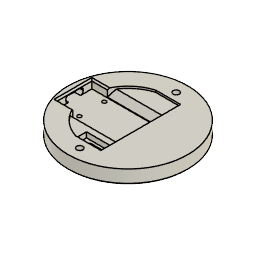
DialScroll (Autodesk Fusion 360 design; units mm, degrees)
Autodesk Fusion 360 part; units mm, degrees
sketch "Sketch1" plane through (0, 0, 0) normal (0, 0, 1) x (1, 0, 0)
  circle A0 centre (0, 0) radius 22.5
  circle A1 centre (0, 0) radius 29
  dimension "d1" = 45
  dimension "d2" = 58
  constraint coincident A0.centre A1.centre
  measures "d1" diameter of A0
  measures "d2" diameter of A1
extrude "Extrude1" add sketch "Sketch1" along normal blind 7 makes body 1
chamfer "Chamfer1" distance 1 angle 45 4 edges at (-27.0375, -10.4868, 7) (-27.0375, -10.4868, 0) (-20.9774, 8.1363, 7) (-20.9774, 8.1363, 0) on bodies 1
ref_plane "WorkPlane1" through (0, 0, -2) normal (0, 0, -1) x (-1, 0, 0)
sketch "Sketch2" plane through (0, 0, -2) normal (0, 0, -1) x (-1, 0, 0)
  line L0 (-21.5, 15) -> (21.5, 15)
  line L1 (21.5, 15) -> (21.5, -15)
  line L2 (21.5, -15) -> (-21.5, -15)
  line L3 (-21.5, -15) -> (-21.5, 15)
  line L4 (-21.5, 15) -> (21.5, -15) construction
  line L5 (21.5, 15) -> (-21.5, -15) construction
  dimension "d7" = 43
  dimension "d8" = 30
  constraint horizontal L0
  constraint perpendicular L0 L1
  constraint parallel L0 L2
  constraint parallel L1 L3
  constraint coincident L4 origin
  constraint coincident L5 origin
  measures "d7" distance of L1.end L2.end
  measures "d8" distance of L0.end L1.end
extrude "Extrude2" add sketch "Sketch2" along normal blind 10 separate body makes body 2
ref_plane "WorkPlane2" through (0, 0, -12.3) normal (0, 0, -1) x (-1, 0, 0)
sketch "Sketch3" plane through (0, 0, -12.3) normal (0, 0, -1) x (-1, 0, 0)
  line L0 (-16.75, 9) -> (16.75, 9)
  line L1 (16.75, 9) -> (16.75, -9)
  line L2 (16.75, -9) -> (-16.75, -9)
  line L3 (-16.75, -9) -> (-16.75, 9)
  line L4 (-16.75, 9) -> (16.75, -9) construction
  line L5 (16.75, 9) -> (-16.75, -9) construction
  dimension "d12" = 33.5
  dimension "d13" = 18
  constraint horizontal L0
  constraint perpendicular L0 L1
  constraint parallel L0 L2
  constraint parallel L1 L3
  constraint coincident L4 origin
  constraint coincident L5 origin
  measures "d12" distance of L1.end L2.end
  measures "d13" distance of L0.end L1.end
extrude "Extrude3" add sketch "Sketch3" along normal blind 4.3 separate body makes body 3
ref_plane "WorkPlane4" through (0, 0, 7.6) normal (0, 0, 1) x (1, 0, 0)
sketch "Sketch6" plane through (0, 0, 7.6) normal (0, 0, 1) x (1, 0, 0)
  circle A0 centre (0, 0) radius 29
  circle A1 centre (0, 0) radius 31
  dimension "d23" = 58
  dimension "d24" = 2
  constraint coincident A0.centre A1.centre
  measures "d23" diameter of A0
extrude "Extrude4" add sketch "Sketch6" along normal blind 2 separate body contours A0 | A1 makes body 4
sketch "Sketch7" plane through (0, 0, 7.6) normal (0, 0, -1) x (1, 0, 0)
  circle A0 centre (0, 0) radius 31
  circle A1 centre (0, 0) radius 29.8
  dimension "d27" = -1.2
extrude "Extrude5" add sketch "Sketch7" along normal blind 19.6 bodies 4
sketch "Sketch8" plane through (0, 0, 7.6) normal (0, 0, -1) x (1, 0, 0)
  circle A0 centre (0, 0) radius 29.8
  circle A1 centre (0, 0) radius 26.8
  dimension "d30" = -3
extrude "Extrude6" add sketch "Sketch8" along normal blind 0.6 bodies 4
sketch "Sketch9" plane through (0, 0, 7) normal (0, 0, -1) x (1, 0, 0)
  circle A0 centre (0, 0) radius 26.8
  circle A1 centre (0, 0) radius 29.8
  circle A2 centre (0, 0) radius 29
  dimension "d33" = -0.8
extrude "Extrude7" add sketch "Sketch9" along normal blind 5.8 contours A1 bodies 4
fillet "Fillet1" radius 0.5 1 edges at (-27.0375, 10.4868, 7) on bodies 4
fillet "Fillet2" radius 4 1 edges at (-28.9021, -11.2101, 9.6) on bodies 4
sketch "Sketch10" plane through (0, 0, 7.6) normal (0, 0, -1) x (1, 0, 0)
  circle A0 centre (0, 0) radius 26.8
  circle A1 centre (0, 0) radius 2.05
  circle A2 centre (0, 0) radius 4.05
  dimension "d40" = 4.1
  dimension "d41" = 2
  constraint coincident A0.centre A1.centre
  measures "d40" diameter of A1
extrude "Extrude8" add sketch "Sketch10" along normal blind 2 contours A2 bodies 4
chamfer "Chamfer2" distance 0.8 angle 45 1 edges at (-1.9113, -0.7413, 5.6) on bodies 4
chamfer "Chamfer3" distance 2 angle 45 1 edges at (-3.7759, -1.4645, 7.6) on bodies 4
ref_plane "WorkPlane5" through (0, 0, 4.6) normal (0, 0, -1) x (-1, 0, 0)
sketch "Sketch11" plane through (0, 0, 4.6) normal (0, 0, -1) x (-1, 0, 0)
  line L0 (11.5, -11.5) -> (-11.5, -11.5)
  line L1 (-11.5, -11.5) -> (-11.5, 11.5)
  line L2 (-11.5, 11.5) -> (11.5, 11.5)
  line L3 (11.5, 11.5) -> (11.5, -11.5)
  line L4 (11.5, -11.5) -> (-11.5, 11.5) construction
  line L5 (-11.5, -11.5) -> (11.5, 11.5) construction
  circle A0 centre (-8.9, 8.9) radius 1.2
  circle A1 centre (8.9, 8.9) radius 1.2
  circle A2 centre (-8.9, -8.9) radius 1.2
  circle A3 centre (8.9, -8.9) radius 1.2
  dimension "d49" = 23
  dimension "d50" = 23
  dimension "d51" = 2.4
  dimension "d52" = 2.6
  dimension "d53" = 2.4
  dimension "d54" = 2.4
  dimension "d55" = 2.4
  dimension "d56" = 2.6
  dimension "d57" = 2.6
  dimension "d58" = 2.6
  constraint horizontal L0
  constraint perpendicular L0 L1
  constraint parallel L0 L2
  constraint parallel L1 L3
  constraint coincident L4 origin
  constraint coincident L5 origin
  constraint coincident L4 A0.centre
  constraint coincident L5 A1.centre
  constraint coincident L5 A2.centre
  constraint coincident L4 A3.centre
  measures "d49" distance of L1.end L2.end
  measures "d50" distance of L0.end L1.end
  measures "d51" diameter of A0
  measures "d52" distance of L1 A0.centre
  measures "d53" diameter of A1
  measures "d54" diameter of A2
  measures "d55" diameter of A3
  measures "d56" distance of L3 A1.centre
  measures "d57" distance of L3 A3.centre
  measures "d58" distance of L1 A2.centre
extrude "Extrude9" add sketch "Sketch11" along normal blind 1.6 separate body makes body 5
fillet "Fillet4" radius 1.8 4 edges at (11.5, 11.5, 3.8) (-11.5, 11.5, 3.8) (-11.5, -11.5, 3.8) (11.5, -11.5, 3.8) on bodies 5
extrude "Extrude10" add 1 faces at (-0.5164, -0.0252, 7.6) along direction (0, 0, -1) blind 2 separate body on bodies 4 makes body 6
ref_plane "WorkPlane6" through (0, 0, -0.3) normal (0, 0, -1) x (-1, 0, 0)
sketch "Sketch13" plane through (0, 0, -0.3) normal (0, 0, -1) x (-1, 0, 0)
  circle A0 centre (0, 0) radius 29
  dimension "d66" = 58
  constraint coincident A0.centre origin
  measures "d66" diameter of A0
extrude "Extrude11" add sketch "Sketch13" along normal blind 2 separate body makes body 7
sketch "Sketch14" plane through (0, 0, -0.3) normal (0, 0, 1) x (-1, 0, 0)
  circle A0 centre (0, 0) radius 29
  circle A1 centre (0, 0) radius 22.5
  circle A2 centre (0, 0) radius 20.5
  dimension "d69" = 45
  dimension "d70" = -2
  constraint coincident A0.centre A1.centre
  measures "d69" diameter of A1
extrude "Extrude12" add sketch "Sketch14" along normal blind 7 contours A1 bodies 1 7
fillet "Fillet6" radius 0.5 1 edges at (20.9774, 8.1363, 6.7) on bodies 1
fillet "Fillet8" radius 0.5 1 edges at (27.0375, -10.4868, -0.3) on bodies 1 7
extrude "Extrude15" add 1 faces at (8.3085, 6.854, -2.3) along direction (0, 0, -1) blind 9.7 on bodies 1 bodies 1
combine "Combine2" operation cut target body 1 tool bodies 2 keep tools
extrude "Extrude20" cut 1 faces at (-8.0163, 5.1011, -0.3) along direction (0, 0, -1) blind 15 on bodies 1 bodies 1
sketch "Sketch25" plane through (0, 0, -0.3) normal (0, 0, 1) x (-1, 0, 0)
  circle A0 centre (0, 0) radius 22.5
  circle A1 centre (0, 0) radius 28.5
  circle A2 centre (0, 0) radius 25.5
  dimension "d117" = 3
extrude "Extrude21" add sketch "Sketch25" along normal blind 0.3 contours A2 bodies 1
extrude "Extrude22" add 1 faces at (23.5705, -2.8493, -12) along direction (0, 0, -1) blind 0.6 on bodies 1 bodies 1
move_body "Move1" bodies 3 to x (1, 0, 0) y (0, 1, 0) z (0, 0, 1) at (0, 0, -0.3)
sketch "Sketch27" plane through (0, 0, 6.7) normal (0, 0, 1) x (-1, 0, 0)
  circle A0 centre (0, 0) radius 20.5
  circle A1 centre (0, 0) radius 22
  circle A2 centre (0, 0) radius 9.5
  dimension "d122" = -11
extrude "Extrude23" add sketch "Sketch27" against normal blind 3.3 contours A0 bodies 1
move_body "Move2" bodies 5 to x (1, 0, 0) y (0, 1, 0) z (0, 0, 1) at (0, 0, -0.9)
sketch "Sketch29" plane through (0, 0, 3.4) normal (0, 0, -1) x (1, 0, 0)
  circle A0 centre (0, 0) radius 9.5
  circle A1 centre (0, 0) radius 20.5
  circle A2 centre (0, 0) radius 11.5
  dimension "d125" = 2
extrude "Extrude24" cut sketch "Sketch29" against normal blind 0.009 contours A2 bodies 1
sketch "Sketch30" plane through (0, 0, 2.1) normal (0, 0, -1) x (1, 0, 0)
  arc A0 (11.5, 9.7) -> (9.7, 11.5) centre (9.7, 9.7) ccw
  line L0 (9.7, 11.5) -> (-9.7, 11.5)
  arc A1 (-9.7, 11.5) -> (-11.5, 9.7) centre (-9.7, 9.7) ccw
  line L1 (-11.5, 9.7) -> (-11.5, -9.7)
  arc A2 (-11.5, -9.7) -> (-9.7, -11.5) centre (-9.7, -9.7) ccw
  line L2 (-9.7, -11.5) -> (9.7, -11.5)
  arc A3 (9.7, -11.5) -> (11.5, -9.7) centre (9.7, -9.7) ccw
  line L3 (11.5, -9.7) -> (11.5, 9.7)
  circle A4 centre (8.9, -8.9) radius 1.2
  circle A5 centre (-8.9, 8.9) radius 1.2
  circle A6 centre (8.9, 8.9) radius 1.2
  circle A7 centre (-8.9, -8.9) radius 1.2
  circle A8 centre (-8.9, 8.9) radius 0.9
  circle A9 centre (8.9, 8.9) radius 0.9
  circle A10 centre (-8.9, -8.9) radius 0.9
  circle A11 centre (8.9, -8.9) radius 0.9
  dimension "d134" = 1.8
  dimension "d135" = 1.8
  dimension "d136" = 1.8
  dimension "d137" = 1.8
  constraint concentric A5 A8
  constraint concentric A6 A9
  constraint concentric A7 A10
  constraint concentric A4 A11
  measures "d134" diameter of A8
  measures "d135" diameter of A9
  measures "d136" diameter of A10
  measures "d137" diameter of A11
extrude "Extrude25" cut sketch "Sketch30" against normal blind 10 contours A8 | A9 | A10 | A11 bodies 1
sketch "Sketch31" plane through (0, 0, -12.6) normal (0, 0, -1) x (1, 0, 0)
  arc A0 (-13.9732, -15) -> (13.9732, -15) centre (0, 0) ccw
  line L0 (-13.9732, -15) -> (-21.5, -15)
  line L1 (-21.5, -15) -> (-21.5, 15)
  line L2 (-21.5, 15) -> (-13.9732, 15)
  arc A1 (13.9732, 15) -> (-13.9732, 15) centre (0, 0) ccw
  line L3 (13.9732, 15) -> (21.5, 15)
  line L4 (21.5, 15) -> (21.5, -15)
  line L5 (21.5, -15) -> (13.9732, -15)
  circle A2 centre (0, 0) radius 29
  circle A3 centre (0, 0) radius 31
  dimension "d140" = 2
extrude "Extrude26" add sketch "Sketch31" along normal blind 7 separate body contours A2 | A3 makes body 8
ref_plane "WorkPlane7" through (0, 0, 7) normal (0, 0, 1) x (1, 0, 0)
sketch "Sketch32" plane through (0, 0, 7) normal (0, 0, 1) x (1, 0, 0)
  circle A0 centre (0, 0) radius 22.5
  circle A1 centre (0, 0) radius 29
  dimension "d144" = 45
  dimension "d145" = 58
  constraint coincident A0.centre A1.centre
  measures "d144" diameter of A0
  measures "d145" diameter of A1
extrude "Extrude27" cut sketch "Sketch32" against normal blind 7 bodies 1
sketch "Sketch33" plane through (0, 0, 0) normal (0, 0, 1) x (-1, 0, 0)
  circle A0 centre (0, 0) radius 25.5
  circle A1 centre (0, 0) radius 22.5
  circle A2 centre (0, 0) radius 22.5
  circle A3 centre (0, 0) radius 29
  dimension "d148" = 45
  dimension "d149" = 58
  constraint coincident A0.centre A1.centre
  measures "d148" diameter of A2
  measures "d149" diameter of A3
extrude "Extrude28" add sketch "Sketch33" along normal blind 7 separate body contours A0 | A3 makes body 9
chamfer "Chamfer4" distance 1 angle 45 4 edges at (27.0375, 10.4868, 7) (20.9774, -8.1363, 7) (20.9774, -8.1363, 0) (27.0375, 10.4868, 0) on bodies 9
sketch "Sketch34" plane through (0, 0, -19.6) normal (0, 0, -1) x (1, 0, 0)
  arc A0 (13.9732, 15) -> (-13.9732, 15) centre (0, 0) ccw
  line L0 (13.9732, 15) -> (21.5, 15)
  line L1 (21.5, 15) -> (21.5, -15)
  line L2 (21.5, -15) -> (13.9732, -15)
  arc A1 (-13.9732, -15) -> (13.9732, -15) centre (0, 0) ccw
  line L3 (-13.9732, -15) -> (-21.5, -15)
  line L4 (-21.5, -15) -> (-21.5, 15)
  line L5 (-21.5, 15) -> (-13.9732, 15)
  circle A2 centre (0, 0) radius 31
  circle A3 centre (0, 0) radius 31
  dimension "d153" = 62
  constraint coincident A0.centre A1.centre
  measures "d153" diameter of A3
extrude "Extrude29" add sketch "Sketch34" against normal blind 3 contours A0 L0 L1 L2 A1 L3 L4 L5 | A2 A3 bodies 8
sketch "Sketch35" plane through (-16.75, 0, 0) normal (-1, 0, 0) x (0, -1, 0)
  line L0 (9, -12.6) -> (-9, -12.6)
  line L1 (-9, -12.6) -> (-9, -16.9)
  line L2 (-9, -16.9) -> (9, -16.9)
  line L3 (9, -16.9) -> (9, -12.6)
  line L4 (4.55, -20.3) -> (-4.55, -20.3)
  line L5 (-4.55, -20.3) -> (-4.55, -13.5)
  line L6 (-4.55, -13.5) -> (4.55, -13.5)
  line L7 (4.55, -13.5) -> (4.55, -20.3)
  line L8 (4.55, -20.3) -> (-4.55, -13.5) construction
  line L9 (-4.55, -20.3) -> (4.55, -13.5) construction
  point P0 (0, -16.9)
  dimension "d156" = 9.1
  dimension "d157" = 6.8
  constraint horizontal L4
  constraint perpendicular L4 L5
  constraint parallel L4 L6
  constraint parallel L5 L7
  constraint coincident L8 P0
  constraint coincident L9 P0
  constraint midpoint L2 P0
  measures "d156" distance of L5.end L6.end
  measures "d157" distance of L4.end L5.end
extrude "Extrude30" add sketch "Sketch35" along normal blind 4 contours L2 L5 L6 L7 bodies 3
move_body "Move3" bodies 3 to x (1, 0, 0) y (0, 1, 0) z (0, 0, 1) at (-11, 0, 0)
extrude "Extrude31" add 1 faces at (-0.6191, -5, -16.6) along direction (0, 0, 1) blind 4 on bodies 8 bodies 8
fillet "Fillet13" radius 1.5 4 edges at (-29.75, 4.55, -13.5) (-29.75, 4.55, -16.9) (-29.75, -4.55, -16.9) (-29.75, -4.55, -13.5) on bodies 3
sketch "Sketch38" plane through (0, 0, -19.6) normal (0, 0, -1) x (1, 0, 0)
  circle A0 centre (0, 0) radius 31
  circle A1 centre (0, -25) radius 1.35
  circle A2 centre (0, 25) radius 1.35
  dimension "d168" = 2.7
  dimension "d169" = 2.7
  dimension "d170" = 25
  dimension "d171" = 25
  measures "d168" diameter of A1
  measures "d169" diameter of A2
  measures "d170" distance of A0.centre A1.centre
  measures "d171" distance of A0.centre A2.centre
extrude "Extrude32" cut sketch "Sketch38" against normal blind 16 contours A1 | A2 bodies 1 8
sketch "Sketch39" plane through (0, 0, -19.6) normal (0, 0, -1) x (1, 0, 0)
  circle A0 centre (0, 25) radius 1.35
  circle A1 centre (0, -25) radius 1.35
  circle A2 centre (0, 0) radius 31
  circle A3 centre (0, 25) radius 1.6
  circle A4 centre (0, -25) radius 1.6
  dimension "d174" = 3.2
  dimension "d175" = 3.2
  constraint concentric A0 A3
  constraint concentric A1 A4
  measures "d174" diameter of A3
  measures "d175" diameter of A4
extrude "Extrude33" cut sketch "Sketch39" against normal blind 8 contours A3 | A4 bodies 8
sketch "Sketch40" plane through (0, 0, -19.6) normal (0, 0, -1) x (1, 0, 0)
  circle A0 centre (0, 25) radius 1.6
  circle A1 centre (0, -25) radius 1.6
  circle A2 centre (0, 0) radius 31
  circle A3 centre (0, 25) radius 3.5
  circle A4 centre (0, -25) radius 3.5
  dimension "d178" = 7
  dimension "d179" = 7
  constraint concentric A0 A3
  constraint concentric A1 A4
  measures "d178" diameter of A3
  measures "d179" diameter of A4
extrude "Extrude34" cut sketch "Sketch40" against normal blind 4 contours A3 | A4 bodies 8
combine "Combine7" operation cut target body 8 tool bodies 3 keep tools
chamfer "Chamfer7" distance 0.5 angle 45 2 edges at (-3.2631, 23.7343, -19.6) (-3.2631, -26.2657, -19.6) on bodies 8
sketch "Sketch41" plane through (0, 0, -12.6) normal (0, 0, 1) x (-1, 0, 0)
  line L0 (-5.75, -9) -> (-5.75, 9)
  line L1 (-5.75, 9) -> (27.75, 9)
  line L2 (27.75, 9) -> (27.75, -9)
  line L3 (27.75, -9) -> (-5.75, -9)
  circle A0 centre (0, 25) radius 1.6
  circle A1 centre (0, -25) radius 1.6
  circle A2 centre (0, 0) radius 31
  line L4 (0, -15) -> (6.6, -15)
  line L5 (6.6, -15) -> (6.6, -20.6)
  line L6 (6.6, -20.6) -> (0, -20.6)
  line L7 (0, -20.6) -> (0, -15)
  line L8 (0, -15) -> (-6.6, -15)
  line L9 (-6.6, -15) -> (-6.6, -20.6)
  line L10 (-6.6, -20.6) -> (0, -20.6)
  line L11 (0, -20.6) -> (0, -15)
  dimension "d185" = 6.6
  dimension "d186" = 5.6
  dimension "d229" = 5.6
  constraint horizontal L4
  constraint vertical L5
  constraint horizontal L6
  constraint vertical L7
  constraint horizontal L8
  constraint vertical L9
  constraint horizontal L10
  constraint vertical L11
  measures "d185" distance of L4.start L4.end
  measures "d186" distance of L4.start L6.end
  measures "d229" distance of L4.start L6.end
sketch "Sketch45" plane through (0, 0, -12.6) normal (0, 0, 1) x (-1, 0, 0)
  line L0 (-5.75, -9) -> (-5.75, 9)
  line L1 (-5.75, 9) -> (27.75, 9)
  line L2 (27.75, 9) -> (27.75, -9)
  line L3 (27.75, -9) -> (-5.75, -9)
  circle A0 centre (0, 25) radius 1.6
  circle A1 centre (0, -25) radius 1.6
  circle A2 centre (0, 0) radius 31
  line L4 (0, 15) -> (-6.55, 15)
  line L5 (-6.55, 15) -> (-6.55, 20.6)
  line L6 (-6.55, 20.6) -> (0, 20.6)
  line L7 (0, 20.6) -> (0, 15)
  line L8 (0, 15) -> (6.55, 15)
  line L9 (6.55, 15) -> (6.55, 20.6)
  line L10 (6.55, 20.6) -> (0, 20.6)
  line L11 (0, 20.6) -> (0, 15)
  dimension "d198" = 6.55
  dimension "d199" = 5.6
  dimension "d200" = 5.6
  dimension "d230" = 6.55
  constraint horizontal L4
  constraint vertical L5
  constraint horizontal L6
  constraint vertical L7
  constraint horizontal L8
  constraint vertical L9
  constraint horizontal L10
  constraint vertical L11
  measures "d198" distance of L4.start L4.end
  measures "d199" distance of L4.start L6.end
  measures "d200" distance of L4.start L6.end
  measures "d230" distance of L9 L11
extrude "Extrude39" cut sketch "Sketch45" against normal blind 3.7 contours L4 L5 L6 L7 L11 | L7 L8 L9 L10 L11 bodies 8
sketch "Sketch46" plane through (0, 0, -16.3) normal (0, 0, 1) x (-1, 0, 0)
  line L0 (-6.55, 15) -> (6.55, 15)
  line L1 (6.55, 15) -> (6.55, 20.6)
  line L2 (6.55, 20.6) -> (-6.55, 20.6)
  line L3 (-6.55, 20.6) -> (-6.55, 15)
  line L4 (-3.4, 19.2) -> (3.4, 19.2)
  line L5 (3.4, 19.2) -> (3.4, 16.4)
  line L6 (3.4, 16.4) -> (-3.4, 16.4)
  line L7 (-3.4, 16.4) -> (-3.4, 19.2)
  line L8 (-3.4, 19.2) -> (3.4, 16.4) construction
  line L9 (3.4, 19.2) -> (-3.4, 16.4) construction
  point P0 (0, 17.8)
  dimension "d203" = 6.8
  dimension "d204" = 2.8
  dimension "d205" = 2.8
  constraint horizontal L4
  constraint perpendicular L4 L5
  constraint parallel L4 L6
  constraint parallel L5 L7
  constraint coincident L8 P0
  constraint coincident L9 P0
  measures "d203" distance of L5.end L6.end
  measures "d204" distance of L4.end L5.end
  measures "d205" distance of L2 P0
extrude "Extrude40" cut sketch "Sketch46" against normal blind 4 contours L4 L5 L6 L7 bodies 8
sketch "Sketch49" plane through (0, 0, -12.6) normal (0, 0, 1) x (-1, 0, 0)
  line L0 (6.55, 20.6) -> (6.55, 15)
  line L1 (6.55, 15) -> (-6.55, 15)
  line L2 (-6.55, 15) -> (-6.55, 20.6)
  line L3 (-6.55, 20.6) -> (6.55, 20.6)
  line L4 (-5.75, -9) -> (-5.75, 9)
  line L5 (-5.75, 9) -> (27.75, 9)
  line L6 (27.75, 9) -> (27.75, -9)
  line L7 (27.75, -9) -> (-5.75, -9)
  circle A0 centre (0, 25) radius 1.6
  circle A1 centre (0, -25) radius 1.6
  circle A2 centre (0, 0) radius 31
  line L8 (-5.75, 9) -> (6.55, 9)
  line L9 (6.55, 9) -> (6.55, 15)
  line L10 (6.55, 15) -> (-5.75, 15)
  line L11 (-5.75, 15) -> (-5.75, 9)
  arc A3 (19.6536, 9) -> (6.55, 20.6) centre (0, 0) ccw
  constraint horizontal L8
  constraint vertical L9
  constraint horizontal L10
  constraint vertical L11
  constraint coincident L0.end L1.start
  constraint coincident L4.end L5.start
  constraint coincident L5 A3.start
  constraint coincident L0.start L3.end
  constraint coincident A2.centre A3.centre
extrude "Extrude42" cut sketch "Sketch49" against normal blind 1 contours L0 L5 L9 A3 | L1 L5 L8 L9 L10 L11 bodies 8
sketch "Sketch50" plane through (0, 0, -16.9) normal (0, 0, 1) x (-1, 0, 0)
  arc A0 (30.8496, -3.05) -> (30.8496, 3.05) centre (0, 0) ccw
  line L0 (30.8496, 3.05) -> (27.75, 3.05)
  line L1 (27.75, 3.05) -> (27.75, 9)
  line L2 (27.75, 9) -> (-5.75, 9)
  line L3 (-5.75, 9) -> (-5.75, -9)
  line L4 (-5.75, -9) -> (27.75, -9)
  line L5 (27.75, -9) -> (27.75, -3.05)
  line L6 (27.75, -3.05) -> (30.8496, -3.05)
  circle A1 centre (18.75, -6.5) radius 1
  circle A2 centre (18.75, 6.5) radius 1
  line L7 (27.75, 9) -> (27.75, -9)
  dimension "d212" = 2
  dimension "d213" = 2
  dimension "d214" = 2.5
  dimension "d215" = 2.5
  dimension "d216" = 9
  dimension "d217" = 9
  measures "d212" diameter of A1
  measures "d213" diameter of A2
  measures "d214" distance of L4 A1.centre
  measures "d215" distance of L2 A2.centre
  measures "d216" distance of A1.centre L7
  measures "d217" distance of A2.centre L7
extrude "Extrude43" cut sketch "Sketch50" against normal blind 5 contours A1 | A2 bodies 8
sketch "Sketch52" plane through (0, 0, -12.6) normal (0, 0, 1) x (-1, 0, 0)
  circle A0 centre (0, 0) radius 31
  circle A1 centre (0, -25) radius 1.6
  circle A2 centre (0, 25) radius 1.6
  arc A3 (19.6536, 9) -> (6.55, 20.6) centre (0, 0) ccw
  line L0 (19.6536, 9) -> (27.75, 9)
  line L1 (27.75, 9) -> (27.75, -9)
  line L2 (27.75, -9) -> (-5.75, -9)
  line L3 (-5.75, -9) -> (-5.75, 15)
  line L4 (-5.75, 15) -> (-6.55, 15)
  line L5 (-6.55, 15) -> (-6.55, 20.6)
  line L6 (-6.55, 20.6) -> (6.55, 20.6)
  line L7 (-5.75, -9) -> (6.35, -9)
  line L8 (6.35, -9) -> (6.35, -20.7)
  line L9 (6.35, -20.7) -> (-5.75, -20.7)
  line L10 (-5.75, -20.7) -> (-5.75, -9)
  arc A4 (6.35, -20.7) -> (19.693, -9) centre (0, 0) ccw
  dimension "d220" = 12.1
  dimension "d221" = 11.7
  constraint horizontal L7
  constraint vertical L8
  constraint horizontal L9
  constraint vertical L10
  constraint coincident L2.end L3.start
  constraint coincident L2 A4.end
  constraint coincident A0.centre A3.centre
  measures "d220" distance of L2.end L7.end
  measures "d221" distance of L2.end L9.end
extrude "Extrude44" cut sketch "Sketch52" against normal blind 1 contours L2 L8 A4 | L2 L7 L8 L9 L10 bodies 8
chamfer "Chamfer8" distance 3 angle 45 2 edges at (-6.9715, 9, -13.6) (-6.9518, -9, -13.6) on bodies 8
sketch "Sketch53" plane through (0, 0, -19.6) normal (0, 0, -1) x (1, 0, 0)
  circle A0 centre (-18.75, 6.5) radius 1
  circle A1 centre (-18.75, -6.5) radius 1
  line L0 (-3.4, 16.4) -> (-3.4, 19.2)
  line L1 (-3.4, 19.2) -> (3.4, 19.2)
  line L2 (3.4, 19.2) -> (3.4, 16.4)
  line L3 (3.4, 16.4) -> (-3.4, 16.4)
  circle A2 centre (0, -25) radius 4
  circle A3 centre (0, 0) radius 31
  circle A4 centre (0, 25) radius 4
  line L4 (-4.9, 20.7) -> (4.9, 20.7)
  line L5 (4.9, 20.7) -> (4.9, 14.9)
  line L6 (4.9, 14.9) -> (-4.9, 14.9)
  line L7 (-4.9, 14.9) -> (-4.9, 20.7)
  dimension "d225" = -1.5
extrude "Extrude45" cut sketch "Sketch53" against normal blind 1.5 contours L4 L5 L6 L7 bodies 8
chamfer "Chamfer9" distance 1.5 angle 45 4 edges at (0, -20.7, -18.1) (4.9, -17.8, -18.1) (-4.9, -17.8, -18.1) (0, -14.9, -18.1) on bodies 8
sketch "Sketch55" plane through (0, 0, 7.6) normal (0, 0, -1) x (1, 0, 0)
  circle A0 centre (0, 0) radius 26.8
  circle A1 centre (0, 0) radius 6.05
  line L0 (6, -1) -> (-6, -1)
  line L1 (-6, -1) -> (-6, 1)
  line L2 (-6, 1) -> (6, 1)
  line L3 (6, 1) -> (6, -1)
  line L4 (6, -1) -> (-6, 1) construction
  line L5 (-6, -1) -> (6, 1) construction
  line L6 (1, -6) -> (-1, -6)
  line L7 (-1, -6) -> (-1, 6)
  line L8 (-1, 6) -> (1, 6)
  line L9 (1, 6) -> (1, -6)
  line L10 (1, -6) -> (-1, 6) construction
  line L11 (-1, -6) -> (1, 6) construction
  dimension "d231" = 12
  dimension "d232" = 2
  dimension "d233" = 2
  dimension "d234" = 12
  constraint horizontal L0
  constraint perpendicular L0 L1
  constraint parallel L0 L2
  constraint parallel L1 L3
  constraint coincident L4 A0.centre
  constraint coincident L5 A0.centre
  constraint coincident A0.centre A1.centre
  constraint horizontal L6
  constraint perpendicular L6 L7
  constraint parallel L6 L8
  constraint parallel L7 L9
  constraint coincident L10 A0.centre
  constraint coincident L11 A0.centre
  measures "d231" distance of L1.end L2.end
  measures "d232" distance of L0.end L1.end
  measures "d233" distance of L7.end L8.end
  measures "d234" distance of L6.end L7.end
extrude "Extrude46" cut sketch "Sketch55" along normal blind 2 contours A1 L3 | A1 L0 L2 L3 L9 | A1 L2 L7 L8 L9 | A1 L0 L6 L7 L9 | A1 L8 | A1 L0 L1 L2 L7 | A1 L6 | A1 L1 bodies 4
sketch "Sketch56" plane through (0, 0, -19.6) normal (0, 0, -1) x (1, 0, 0)
  line L0 (4.9, 20.7) -> (4.9, 14.9)
  line L1 (4.9, 14.9) -> (-4.9, 14.9)
  line L2 (-4.9, 14.9) -> (-4.9, 20.7)
  line L3 (-4.9, 20.7) -> (4.9, 20.7)
  circle A0 centre (-18.75, 6.5) radius 1
  circle A1 centre (-18.75, -6.5) radius 1
  circle A2 centre (0, -25) radius 4
  circle A3 centre (0, 0) radius 31
  circle A4 centre (0, 25) radius 4
  circle A5 centre (26, 0) radius 4
  circle A6 centre (13, 22.5167) radius 4
  circle A7 centre (-13, 22.5167) radius 4
  circle A8 centre (-26, 0) radius 4
  circle A9 centre (-13, -22.5167) radius 4
  circle A10 centre (13, -22.5167) radius 4
  dimension "d237" = 8
  dimension "d238" = 26
  dimension "d240" = 360
  measures "d237" diameter of A5
  measures "d238" distance of A3.centre A5.centre
extrude "Extrude47" cut sketch "Sketch56" against normal blind 0.6 contours A5 | A6 | A7 | A8 | A9 | A10 bodies 8
chamfer "Chamfer10" distance 0.8 angle 45 1 edges at (5.75, 2.85, -12.6) on bodies 8
chamfer "Chamfer11" distance 0.8 angle 45 3 edges at (-23.7215, 9, -12.6) (-27.75, 0, -12.6) (-23.7018, -9, -12.6) on bodies 8
chamfer "Chamfer12" distance 0.5 angle 45 1 edges at (-28.9021, 11.2101, -19.6) on bodies 8
hidden bodies 1 2 3 4 5 6 9
equation "d1 = ballring_in_d"
equation "d2 = ballring_out_d"
equation "d3 = ballring_h"
equation "d11 = layer_h"
equation "ballring_out_d = 58 mm"
equation "ballring_in_d = 45 mm"
equation "ballring_h = 7 mm"
equation "layer_h = 0.3 mm"
equation "layer_w = 0.4 mm"
equation "d22 = 2 * layer_h"
equation "d23 = ballring_out_d"
equation "d27 = -2 mm + 2 * layer_w"
equation "d28 = 2 * layer_h + ballring_h + 2 mm + 10 mm"
equation "d31 = 2 * layer_h"
equation "d33 = -2 * layer_w"
equation "d34 = ballring_h - 2 * layer_h * 2"
equation "d52 = 1.4 mm + 1.2 mm"
equation "d65 = layer_h"
equation "d66 = ballring_out_d"
equation "d69 = ballring_in_d"
equation "d71 = ballring_h"
equation "d89 = 10 mm - layer_h"
equation "enc_screw_d = 1.8 mm"
equation "d118 = layer_h"
equation "d120 = layer_h * 2"
equation "d123 = -3 mm - layer_h"
equation "d126 = -layer_h * 3 * 0.01"
equation "d134 = enc_screw_d"
equation "d135 = enc_screw_d"
equation "d136 = enc_screw_d"
equation "d137 = enc_screw_d"
equation "d144 = ballring_in_d"
equation "d145 = ballring_out_d"
equation "d146 = -ballring_h"
equation "d148 = ballring_in_d"
equation "d149 = ballring_out_d"
equation "d150 = ballring_h"
equation "d153 = ballring_out_d + 4 mm"
equation "d172 = -7 mm - 9 mm"
equation "d185 = ( 13.2 / 2 ) * 1 mm"
equation "d198 = ( 13.1 / 2 ) * 1 mm"
equation "d205 = ( 5.6 / 2 ) * 1 mm"
named bodies: "BaseIn", "Battery", "Microcontroller", "Cover", "Encoder", "Magnet", "Base_in", "Base", "Ballring"
